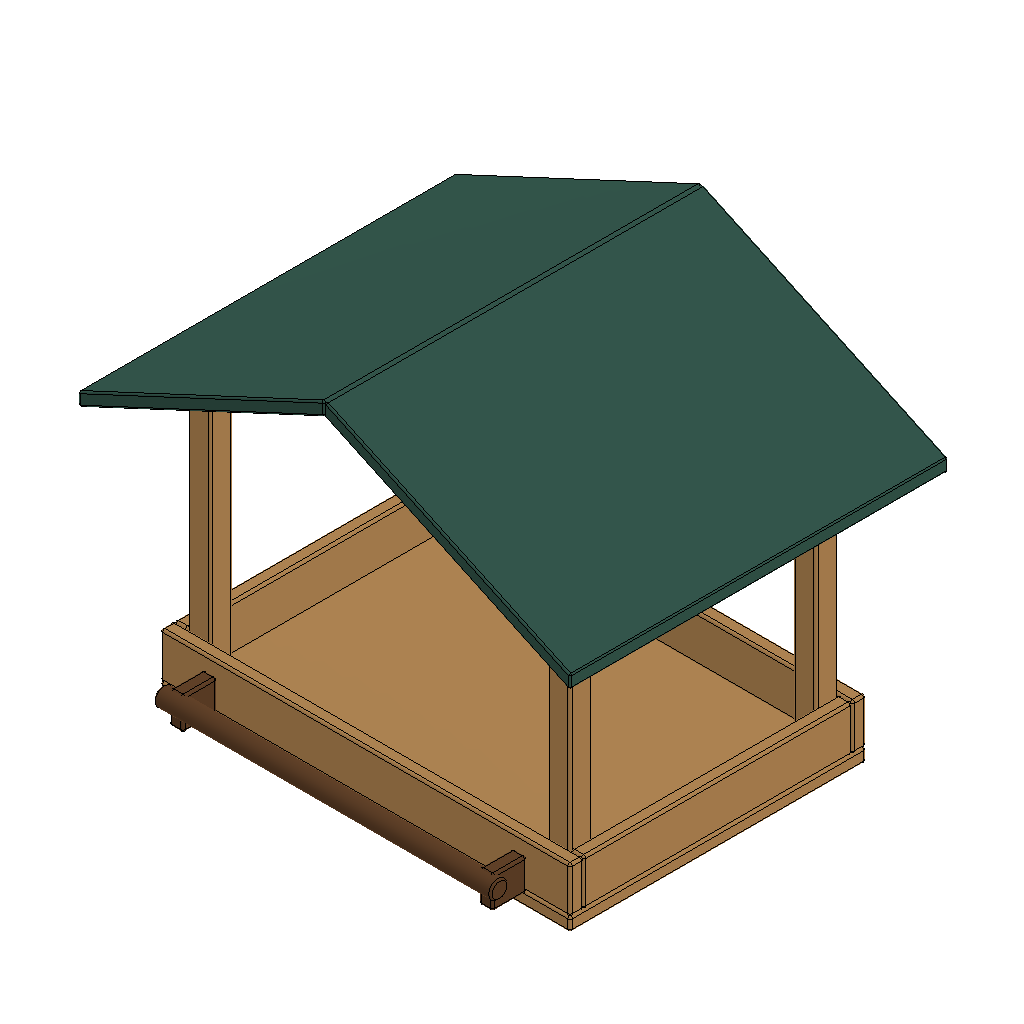
Cedar-Sage-Paramood (Autodesk Fusion 360 design; units mm, degrees)
Autodesk Fusion 360 part; units mm, degrees
sketch "Tray floor outline" plane through (0, 0, 0) normal (0, 0, 1) x (1, 0, 0)
  line L0 (-90, -65) -> (90, -65)
  line L1 (90, -65) -> (90, 65)
  line L2 (90, 65) -> (-90, 65)
  line L3 (-90, 65) -> (-90, -65)
  dimension "d137" = 90
  dimension "d138" = 65
  dimension "d139" = 90
  dimension "d140" = 65
  constraint horizontal L0.start L0.end
  constraint vertical L0.end L1.end
  constraint vertical L0.start L2.end
  constraint horizontal L1.end L2.end
  measures "d137" horizontal distance of origin L0.start
  measures "d138" vertical distance of origin L0.start
  measures "d139" horizontal distance of origin L0.end
  measures "d140" vertical distance of origin L1.end
extrude "Tray — floor" add sketch "Tray floor outline" along normal blind 6 makes body 1
fillet "Tray — floor — softened edges" radius 1 12 edges at (0, 65, 0) (-90, 65, 3) (0, 65, 6) (90, 65, 3) (90, 0, 0) (90, 0, 6) (90, -65, 3) (0, -65, 0) (0, -65, 6) (-90, -65, 3) (-90, 0, 0) (-90, 0, 6) on bodies 1
ref_plane "WorkPlane2" through (0, 0, 6) normal (0, 0, 1) x (1, 0, 0)
sketch "Sketch19" plane through (0, 0, 6) normal (0, 0, 1) x (1, 0, 0)
  line L0 (-90, -65) -> (90, -65)
  line L1 (90, -65) -> (90, -59)
  line L2 (90, -59) -> (-90, -59)
  line L3 (-90, -59) -> (-90, -65)
  dimension "d147" = 90
  dimension "d148" = 65
  dimension "d149" = 90
  dimension "d150" = 59
  constraint horizontal L0.start L0.end
  constraint vertical L0.end L1.end
  constraint vertical L0.start L2.end
  constraint horizontal L1.end L2.end
  measures "d147" horizontal distance of origin L0.start
  measures "d148" vertical distance of origin L0.start
  measures "d149" horizontal distance of origin L0.end
  measures "d150" vertical distance of origin L1.end
extrude "Tray — front rim" add sketch "Sketch19" along normal blind 20 separate body makes body 2
fillet "Tray — front rim — softened edges" radius 1 12 edges at (0, -59, 6) (-90, -59, 16) (0, -59, 26) (90, -59, 16) (90, -62, 6) (90, -62, 26) (90, -65, 16) (0, -65, 6) (0, -65, 26) (-90, -65, 16) (-90, -62, 6) (-90, -62, 26) on bodies 2
sketch "Sketch20" plane through (0, 0, 6) normal (0, 0, 1) x (1, 0, 0)
  line L0 (-90, 59) -> (90, 59)
  line L1 (90, 59) -> (90, 65)
  line L2 (90, 65) -> (-90, 65)
  line L3 (-90, 65) -> (-90, 59)
  dimension "d155" = 90
  dimension "d156" = 59
  dimension "d157" = 90
  dimension "d158" = 65
  constraint horizontal L0.start L0.end
  constraint vertical L0.end L1.end
  constraint vertical L0.start L2.end
  constraint horizontal L1.end L2.end
  measures "d155" horizontal distance of origin L0.start
  measures "d156" vertical distance of origin L0.start
  measures "d157" horizontal distance of origin L0.end
  measures "d158" vertical distance of origin L1.end
extrude "Tray — back rim" add sketch "Sketch20" along normal blind 20 separate body makes body 3
fillet "Tray — back rim — softened edges" radius 1 12 edges at (0, 65, 6) (-90, 65, 16) (0, 65, 26) (90, 65, 16) (90, 62, 6) (90, 62, 26) (90, 59, 16) (0, 59, 6) (0, 59, 26) (-90, 59, 16) (-90, 62, 6) (-90, 62, 26) on bodies 3
sketch "Sketch21" plane through (0, 0, 6) normal (0, 0, 1) x (1, 0, 0)
  line L0 (-90, -59) -> (-84, -59)
  line L1 (-84, -59) -> (-84, 59)
  line L2 (-84, 59) -> (-90, 59)
  line L3 (-90, 59) -> (-90, -59)
  dimension "d163" = 90
  dimension "d164" = 59
  dimension "d165" = 84
  dimension "d166" = 59
  constraint horizontal L0.start L0.end
  constraint vertical L0.end L1.end
  constraint vertical L0.start L2.end
  constraint horizontal L1.end L2.end
  measures "d163" horizontal distance of origin L0.start
  measures "d164" vertical distance of origin L0.start
  measures "d165" horizontal distance of origin L0.end
  measures "d166" vertical distance of origin L1.end
extrude "Tray — left rim" add sketch "Sketch21" along normal blind 20 separate body makes body 4
fillet "Tray — left rim — softened edges" radius 1 12 edges at (-87, 59, 6) (-90, 59, 16) (-87, 59, 26) (-84, 59, 16) (-84, 0, 6) (-84, 0, 26) (-84, -59, 16) (-87, -59, 6) (-87, -59, 26) (-90, -59, 16) (-90, 0, 6) (-90, 0, 26) on bodies 4
sketch "Sketch22" plane through (0, 0, 6) normal (0, 0, 1) x (1, 0, 0)
  line L0 (84, -59) -> (90, -59)
  line L1 (90, -59) -> (90, 59)
  line L2 (90, 59) -> (84, 59)
  line L3 (84, 59) -> (84, -59)
  dimension "d171" = 84
  dimension "d172" = 59
  dimension "d173" = 90
  dimension "d174" = 59
  constraint horizontal L0.start L0.end
  constraint vertical L0.end L1.end
  constraint vertical L0.start L2.end
  constraint horizontal L1.end L2.end
  measures "d171" horizontal distance of origin L0.start
  measures "d172" vertical distance of origin L0.start
  measures "d173" horizontal distance of origin L0.end
  measures "d174" vertical distance of origin L1.end
extrude "Tray — right rim" add sketch "Sketch22" along normal blind 20 separate body makes body 5
fillet "Tray — right rim — softened edges" radius 1 12 edges at (87, 59, 6) (84, 59, 16) (87, 59, 26) (90, 59, 16) (90, 0, 6) (90, 0, 26) (90, -59, 16) (87, -59, 6) (87, -59, 26) (84, -59, 16) (84, 0, 6) (84, 0, 26) on bodies 5
sketch "Sketch23" plane through (0, 0, 6) normal (0, 0, 1) x (1, 0, 0)
  line L0 (-84, -59) -> (-74, -59)
  line L1 (-74, -59) -> (-74, -49)
  line L2 (-74, -49) -> (-84, -49)
  line L3 (-84, -49) -> (-84, -59)
  dimension "d179" = 84
  dimension "d180" = 59
  dimension "d181" = 74
  dimension "d182" = 49
  constraint horizontal L0.start L0.end
  constraint vertical L0.end L1.end
  constraint vertical L0.start L2.end
  constraint horizontal L1.end L2.end
  measures "d179" horizontal distance of origin L0.start
  measures "d180" vertical distance of origin L0.start
  measures "d181" horizontal distance of origin L0.end
  measures "d182" vertical distance of origin L1.end
extrude "Post — left front" add sketch "Sketch23" along normal blind 120 separate body makes body 6
fillet "Post — left front — softened edges" radius 1 12 edges at (-79, -49, 6) (-84, -49, 66) (-79, -49, 126) (-74, -49, 66) (-74, -54, 6) (-74, -54, 126) (-74, -59, 66) (-79, -59, 6) (-79, -59, 126) (-84, -59, 66) (-84, -54, 6) (-84, -54, 126) on bodies 6
sketch "Sketch24" plane through (0, 0, 6) normal (0, 0, 1) x (1, 0, 0)
  line L0 (-84, 49) -> (-74, 49)
  line L1 (-74, 49) -> (-74, 59)
  line L2 (-74, 59) -> (-84, 59)
  line L3 (-84, 59) -> (-84, 49)
  dimension "d187" = 84
  dimension "d188" = 49
  dimension "d189" = 74
  dimension "d190" = 59
  constraint horizontal L0.start L0.end
  constraint vertical L0.end L1.end
  constraint vertical L0.start L2.end
  constraint horizontal L1.end L2.end
  measures "d187" horizontal distance of origin L0.start
  measures "d188" vertical distance of origin L0.start
  measures "d189" horizontal distance of origin L0.end
  measures "d190" vertical distance of origin L1.end
extrude "Post — left back" add sketch "Sketch24" along normal blind 120 separate body makes body 7
fillet "Post — left back — softened edges" radius 1 12 edges at (-79, 59, 6) (-84, 59, 66) (-79, 59, 126) (-74, 59, 66) (-74, 54, 6) (-74, 54, 126) (-74, 49, 66) (-79, 49, 6) (-79, 49, 126) (-84, 49, 66) (-84, 54, 6) (-84, 54, 126) on bodies 7
sketch "Sketch25" plane through (0, 0, 6) normal (0, 0, 1) x (1, 0, 0)
  line L0 (74, -59) -> (84, -59)
  line L1 (84, -59) -> (84, -49)
  line L2 (84, -49) -> (74, -49)
  line L3 (74, -49) -> (74, -59)
  dimension "d195" = 74
  dimension "d196" = 59
  dimension "d197" = 84
  dimension "d198" = 49
  constraint horizontal L0.start L0.end
  constraint vertical L0.end L1.end
  constraint vertical L0.start L2.end
  constraint horizontal L1.end L2.end
  measures "d195" horizontal distance of origin L0.start
  measures "d196" vertical distance of origin L0.start
  measures "d197" horizontal distance of origin L0.end
  measures "d198" vertical distance of origin L1.end
extrude "Post — right front" add sketch "Sketch25" along normal blind 120 separate body makes body 8
fillet "Post — right front — softened edges" radius 1 12 edges at (79, -49, 6) (74, -49, 66) (79, -49, 126) (84, -49, 66) (84, -54, 6) (84, -54, 126) (84, -59, 66) (79, -59, 6) (79, -59, 126) (74, -59, 66) (74, -54, 6) (74, -54, 126) on bodies 8
sketch "Sketch26" plane through (0, 0, 6) normal (0, 0, 1) x (1, 0, 0)
  line L0 (74, 49) -> (84, 49)
  line L1 (84, 49) -> (84, 59)
  line L2 (84, 59) -> (74, 59)
  line L3 (74, 59) -> (74, 49)
  dimension "d203" = 74
  dimension "d204" = 49
  dimension "d205" = 84
  dimension "d206" = 59
  constraint horizontal L0.start L0.end
  constraint vertical L0.end L1.end
  constraint vertical L0.start L2.end
  constraint horizontal L1.end L2.end
  measures "d203" horizontal distance of origin L0.start
  measures "d204" vertical distance of origin L0.start
  measures "d205" horizontal distance of origin L0.end
  measures "d206" vertical distance of origin L1.end
extrude "Post — right back" add sketch "Sketch26" along normal blind 120 separate body makes body 9
fillet "Post — right back — softened edges" radius 1 12 edges at (79, 59, 6) (74, 59, 66) (79, 59, 126) (84, 59, 66) (84, 54, 6) (84, 54, 126) (84, 49, 66) (79, 49, 6) (79, 49, 126) (74, 49, 66) (74, 54, 6) (74, 54, 126) on bodies 9
sketch "Sketch27" plane through (0, 0, 0) normal (0, 1, 0) x (1, 0, 0)
  line L0 (-108, -110.1455) -> (0, -160.5068)
  line L1 (0, -160.5068) -> (0, -166.5068)
  line L2 (0, -166.5068) -> (-108, -116.1455)
  line L3 (-108, -116.1455) -> (-108, -110.1455)
  dimension "d211" = 108
  dimension "d212" = 110.1455
  dimension "d213" = 160.5068
  dimension "d214" = 166.5068
  dimension "d215" = 116.1455
  constraint vertical origin L0.end
  constraint vertical origin L1.end
  constraint vertical L0.start L2.end
  measures "d211" horizontal distance of origin L0.start
  measures "d212" vertical distance of origin L0.start
  measures "d213" vertical distance of origin L0.end
  measures "d214" vertical distance of origin L1.end
  measures "d215" vertical distance of origin L2.end
extrude "Roof — left panel" add sketch "Sketch27" along normal mid plane 166 separate body makes body 10
fillet "Roof — left panel — softened edges" radius 0.75 12 edges at (-54, -83, 141.3262) (-108, -83, 113.1455) (-54, -83, 135.3262) (0, -83, 163.5068) (-108, 0, 116.1455) (-108, 83, 113.1455) (-108, 0, 110.1455) (-54, 83, 135.3262) (0, 0, 160.5068) (0, 83, 163.5068) (0, 0, 166.5068) (-54, 83, 141.3262) on bodies 10
sketch "Sketch28" plane through (0, 0, 0) normal (0, 1, 0) x (1, 0, 0)
  line L0 (108, -110.1455) -> (0, -160.5068)
  line L1 (0, -160.5068) -> (0, -166.5068)
  line L2 (0, -166.5068) -> (108, -116.1455)
  line L3 (108, -116.1455) -> (108, -110.1455)
  dimension "d220" = 108
  dimension "d221" = 110.1455
  dimension "d222" = 160.5068
  dimension "d223" = 166.5068
  dimension "d224" = 116.1455
  constraint vertical origin L0.end
  constraint vertical origin L1.end
  constraint vertical L0.start L2.end
  measures "d220" horizontal distance of origin L0.start
  measures "d221" vertical distance of origin L0.start
  measures "d222" vertical distance of origin L0.end
  measures "d223" vertical distance of origin L1.end
  measures "d224" vertical distance of origin L2.end
extrude "Roof — right panel" add sketch "Sketch28" along normal mid plane 166 separate body makes body 11
fillet "Roof — right panel — softened edges" radius 0.75 12 edges at (108, -83, 113.1455) (54, -83, 141.3262) (0, -83, 163.5068) (54, -83, 135.3262) (108, 0, 116.1455) (54, 83, 141.3262) (0, 0, 166.5068) (0, 83, 163.5068) (0, 0, 160.5068) (54, 83, 135.3262) (108, 0, 110.1455) (108, 83, 113.1455) on bodies 11
sketch "Sketch29" plane through (0, 0, 6) normal (0, 0, 1) x (1, 0, 0)
  line L0 (-71, -80) -> (-65, -80)
  line L1 (-65, -80) -> (-65, -65)
  line L2 (-65, -65) -> (-71, -65)
  line L3 (-71, -65) -> (-71, -80)
  dimension "d229" = 71
  dimension "d230" = 80
  dimension "d231" = 65
  dimension "d232" = 65
  constraint horizontal L0.start L0.end
  constraint vertical L0.end L1.end
  constraint vertical L0.start L2.end
  constraint horizontal L1.end L2.end
  measures "d229" horizontal distance of origin L0.start
  measures "d230" vertical distance of origin L0.start
  measures "d231" horizontal distance of origin L0.end
  measures "d232" vertical distance of origin L1.end
extrude "Perch — support -1" add sketch "Sketch29" along normal blind 14 separate body makes body 12
fillet "Perch — support -1 — softened edges" radius 1 12 edges at (-68, -65, 6) (-71, -65, 13) (-68, -65, 20) (-65, -65, 13) (-65, -72.5, 6) (-65, -72.5, 20) (-65, -80, 13) (-68, -80, 6) (-68, -80, 20) (-71, -80, 13) (-71, -72.5, 6) (-71, -72.5, 20) on bodies 12
sketch "Sketch30" plane through (0, 0, 6) normal (0, 0, 1) x (1, 0, 0)
  line L0 (65, -80) -> (71, -80)
  line L1 (71, -80) -> (71, -65)
  line L2 (71, -65) -> (65, -65)
  line L3 (65, -65) -> (65, -80)
  dimension "d237" = 65
  dimension "d238" = 80
  dimension "d239" = 71
  dimension "d240" = 65
  constraint horizontal L0.start L0.end
  constraint vertical L0.end L1.end
  constraint vertical L0.start L2.end
  constraint horizontal L1.end L2.end
  measures "d237" horizontal distance of origin L0.start
  measures "d238" vertical distance of origin L0.start
  measures "d239" horizontal distance of origin L0.end
  measures "d240" vertical distance of origin L1.end
extrude "Perch — support 1" add sketch "Sketch30" along normal blind 14 separate body makes body 13
fillet "Perch — support 1 — softened edges" radius 1 12 edges at (68, -65, 6) (65, -65, 13) (68, -65, 20) (71, -65, 13) (71, -72.5, 6) (71, -72.5, 20) (71, -80, 13) (68, -80, 6) (68, -80, 20) (65, -80, 13) (65, -72.5, 6) (65, -72.5, 20) on bodies 13
sketch "Sketch31" plane through (0, 0, 0) normal (1, 0, 0) x (0, 0, -1)
  circle A0 centre (-16, -80) radius 4
  dimension "d245" = 16
  dimension "d246" = 80
  dimension "d247" = 8
  measures "d245" horizontal distance of origin A0.centre
  measures "d246" vertical distance of origin A0.centre
  measures "d247" diameter of A0
extrude "Perch — round landing rail" add sketch "Sketch31" along normal mid plane 148 separate body makes body 14
fillet "Perch — round landing rail — softened edges" radius 0.75 2 edges at (-74, -78.5535, 19.7293) (74, -81.4465, 19.7293) on bodies 14
equation "tray_width = 180 mm" comment "Overall tray width"
equation "tray_depth = 130 mm" comment "Overall tray depth"
equation "tray_base = 6 mm" comment "Floor thickness"
equation "tray_wall = 6 mm" comment "Rim wall thickness"
equation "tray_rim = 20 mm" comment "Rim height above the floor"
equation "post_height = 120 mm" comment "Post height above the floor"
equation "post_size = 10 mm" comment "Square post width"
equation "roof_overhang = 18 mm" comment "Roof overhang on each side"
equation "roof_thickness = 6 mm" comment "Roof panel vertical thickness"
equation "roof_pitch = 25 deg" comment "Roof slope angle"
equation "roof_eave = tray_base + post_height - ( roof_overhang + tray_wall + post_size ) * tan(roof_pitch)" comment "Derived eave elevation"
equation "roof_rise = ( tray_width / 2 + roof_overhang ) * tan(roof_pitch)" comment "Derived gable rise"
equation "perch_offset = 15 mm" comment "Perch offset in front of tray"
equation "perch_diameter = 8 mm" comment "Round perch diameter"
equation "d137 = abs(-tray_width / 2)"
equation "d138 = abs(-tray_depth / 2)"
equation "d139 = abs(tray_width / 2)"
equation "d140 = abs(tray_depth / 2)"
equation "d141 = tray_base"
equation "d144 = tray_wall / 6"
equation "d145 = tray_base"
equation "d147 = abs(-tray_width / 2)"
equation "d148 = abs(-tray_depth / 2)"
equation "d149 = abs(tray_width / 2)"
equation "d150 = abs(-tray_depth / 2 + tray_wall)"
equation "d151 = tray_rim"
equation "d154 = tray_wall / 6"
equation "d155 = abs(-tray_width / 2)"
equation "d156 = abs(tray_depth / 2 - tray_wall)"
equation "d157 = abs(tray_width / 2)"
equation "d158 = abs(tray_depth / 2)"
equation "d159 = tray_rim"
equation "d162 = tray_wall / 6"
equation "d163 = abs(-tray_width / 2)"
equation "d164 = abs(-tray_depth / 2 + tray_wall)"
equation "d165 = abs(-tray_width / 2 + tray_wall)"
equation "d166 = abs(tray_depth / 2 - tray_wall)"
equation "d167 = tray_rim"
equation "d170 = tray_wall / 6"
equation "d171 = abs(tray_width / 2 - tray_wall)"
equation "d172 = abs(-tray_depth / 2 + tray_wall)"
equation "d173 = abs(tray_width / 2)"
equation "d174 = abs(tray_depth / 2 - tray_wall)"
equation "d175 = tray_rim"
equation "d178 = tray_wall / 6"
equation "d179 = abs(-tray_width / 2 + tray_wall)"
equation "d180 = abs(-tray_depth / 2 + tray_wall)"
equation "d181 = abs(-tray_width / 2 + tray_wall + post_size)"
equation "d182 = abs(-tray_depth / 2 + tray_wall + post_size)"
equation "d183 = post_height"
equation "d186 = tray_wall / 6"
equation "d187 = abs(-tray_width / 2 + tray_wall)"
equation "d188 = abs(tray_depth / 2 - tray_wall - post_size)"
equation "d189 = abs(-tray_width / 2 + tray_wall + post_size)"
equation "d190 = abs(tray_depth / 2 - tray_wall)"
equation "d191 = post_height"
equation "d194 = tray_wall / 6"
equation "d195 = abs(tray_width / 2 - tray_wall - post_size)"
equation "d196 = abs(-tray_depth / 2 + tray_wall)"
equation "d197 = abs(tray_width / 2 - tray_wall)"
equation "d198 = abs(-tray_depth / 2 + tray_wall + post_size)"
equation "d199 = post_height"
equation "d202 = tray_wall / 6"
equation "d203 = abs(tray_width / 2 - tray_wall - post_size)"
equation "d204 = abs(tray_depth / 2 - tray_wall - post_size)"
equation "d205 = abs(tray_width / 2 - tray_wall)"
equation "d206 = abs(tray_depth / 2 - tray_wall)"
equation "d207 = post_height"
equation "d210 = tray_wall / 6"
equation "d211 = abs(-tray_width / 2 - roof_overhang)"
equation "d212 = abs(-roof_eave)"
equation "d213 = abs(-roof_eave - roof_rise)"
equation "d214 = abs(-roof_eave - roof_rise - roof_thickness)"
equation "d215 = abs(-roof_eave - roof_thickness)"
equation "d216 = tray_depth + 2 * roof_overhang"
equation "d219 = roof_thickness / 8"
equation "d220 = abs(tray_width / 2 + roof_overhang)"
equation "d221 = abs(-roof_eave)"
equation "d222 = abs(-roof_eave - roof_rise)"
equation "d223 = abs(-roof_eave - roof_rise - roof_thickness)"
equation "d224 = abs(-roof_eave - roof_thickness)"
equation "d225 = tray_depth + 2 * roof_overhang"
equation "d228 = roof_thickness / 8"
equation "d229 = abs(( -tray_width / 2 + 2 * tray_wall + post_size ) - tray_wall / 2)"
equation "d230 = abs(-tray_depth / 2 - perch_offset)"
equation "d231 = abs(( -tray_width / 2 + 2 * tray_wall + post_size ) + tray_wall / 2)"
equation "d232 = abs(-tray_depth / 2)"
equation "d233 = tray_rim / 2 + perch_diameter / 2"
equation "d236 = tray_wall / 6"
equation "d237 = abs(( tray_width / 2 - 2 * tray_wall - post_size ) - tray_wall / 2)"
equation "d238 = abs(-tray_depth / 2 - perch_offset)"
equation "d239 = abs(( tray_width / 2 - 2 * tray_wall - post_size ) + tray_wall / 2)"
equation "d240 = abs(-tray_depth / 2)"
equation "d241 = tray_rim / 2 + perch_diameter / 2"
equation "d244 = tray_wall / 6"
equation "d245 = abs(-tray_base - tray_rim / 2)"
equation "d246 = abs(-tray_depth / 2 - perch_offset)"
equation "d247 = perch_diameter"
equation "d248 = tray_width - 2 * tray_wall - 2 * post_size"
equation "d251 = tray_wall / 8"
equation "caption = 'Cedar & Sage'"
equation "post = 4"
equation "caption_variant = 'Classic'"
equation "caption_label = caption + ' / ' + caption_variant"
named bodies: "Tray — floor", "Tray — front rim", "Tray — back rim", "Tray — left rim", "Tray — right rim", "Post — left front", "Post — left back", "Post — right front", "Post — right back", "Roof — left panel", "Roof — right panel", "Perch — support -1", "Perch — support 1", "Perch — round landing rail"
